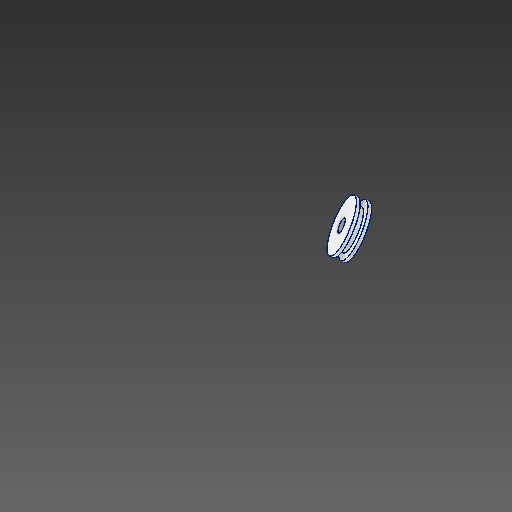
# Autodesk Inventor part: Part5
Saved by Autodesk Inventor 2026.1 (Build 301233020, 233B)
## iProperties
Created: 2026-10-30
Part Number: Part5
Material: Aluminum 6061
Document SubType Name: Modeling
Designer: YmCris
Density: 2.7 g/cm^3
Appearance: Aluminum - Flat
Author: YmCris
Autodesk Inventor part; units mm, degrees
ref_plane "YZ Plane" through (0, 0, 0) normal (1, 0, 0) x (0, 1, 0)
ref_plane "XZ Plane" through (0, 0, 0) normal (0, 1, 0) x (-1, 0, 0)
ref_plane "XY Plane" through (0, 0, 0) normal (0, 0, 1) x (1, 0, 0)
sketch "Sketch1" plane through (0, 0, 0) normal (0, 0, 1) x (1, 0, 0)
  line L0 (3.0048, -32.2023) -> (53.0048, -32.2023)
  line L1 (53.0048, -32.2023) -> (53.0048, -25.7023)
  line L2 (53.0048, -12.7023) -> (53.0048, -6.2023)
  line L3 (53.0048, -6.2023) -> (3.0048, -6.2023)
  line L4 (3.0048, -6.2023) -> (3.0048, -32.2023)
  line L5 (3.0048, -6.2023) -> (3.0048, -27.9972) construction
  line L6 (53.0048, -25.7023) -> (41.0048, -24.2023)
  line L7 (53.0048, -12.7023) -> (41.0048, -14.2023)
  line L8 (41.0048, -14.2023) -> (41.0048, -24.2023)
  point P0 (0, 0)
  point P1 (53.0048, -24.2023)
  point P2 (53.0048, -14.2023)
  dimension "d0" = 50
  dimension "d1" = 6.5
  dimension "d9" = 6.5
  dimension "d10" = 26
  constraints: 18 end point, 3 point on line, 2 horizontal, 2 perpendicular
  measures "d0" distance of L4.end L1.start
  measures "d1" distance of L1.start L1.end
  measures "d9" distance of L2.start L2.end
  measures "d10" distance of L4.end L3.end
revolve "Revolution1" add sketch "Sketch1" angle 360 about axis through (3.0048, -6.2023, 0) along (0, -1, 0)
sketch "Sketch3" plane through (3.0048, -6.2023, 0) normal (0, 1, 0) x (1, 0, 0)
  circle A0 centre (0, 0) radius 12.5
  point P0 (-3.0048, 0)
  dimension "d15" = 25
  constraints: 1 centre point
  measures "d15" diameter of A0
extrude "Extrusion1" cut sketch "Sketch3" against normal blind 26
body "Solid1"
